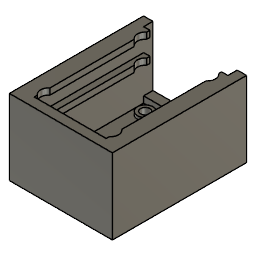
gy-neo6mv2_stand_v1 (Autodesk Fusion 360 design; units mm, degrees)
Autodesk Fusion 360 part; units mm, degrees
sketch "Sketch1" plane through (0, 0, 0) normal (0, 0, 1) x (1, 0, 0)
  line L0 (-13.5, 18.5) -> (13.5, 18.5)
  line L1 (13.5, 18.5) -> (13.5, -18.5)
  line L2 (13.5, -18.5) -> (-13.5, -18.5)
  line L3 (-13.5, -18.5) -> (-13.5, 18.5)
  line L4 (-16.5, 21.5) -> (16.5, 21.5)
  line L5 (16.5, 21.5) -> (16.5, -21.5)
  line L6 (16.5, -21.5) -> (-16.5, -21.5)
  line L7 (-16.5, -21.5) -> (-16.5, 21.5)
  circle A0 centre (-10, 15.5) radius 1.5
  circle A1 centre (10, 15.5) radius 1.5
  circle A2 centre (-10, -15.5) radius 1.5
  circle A3 centre (10, -15.5) radius 1.5
  circle A4 centre (-10, 15.5) radius 2.5
  circle A5 centre (10, 15.5) radius 2.5
  circle A6 centre (-10, -15.5) radius 2.5
  circle A7 centre (10, -15.5) radius 2.5
  line L8 (-13.5, 18.5) -> (-13.5, 21.5)
  line L9 (13.5, 18.5) -> (13.5, 21.5)
  line L10 (13.5, -18.5) -> (11.4824, -18.5)
  line L11 (11.4824, -18.5) -> (11.4824, 18.5)
  line L12 (11.4824, 18.5) -> (13.5, 18.5)
  line L13 (13.5, 18.5) -> (13.5, -18.5)
  line L14 (-13.5, -18.5) -> (-11.5071, -18.5)
  line L15 (-11.5071, -18.5) -> (-11.5071, 18.5)
  line L16 (-11.5071, 18.5) -> (-13.5, 18.5)
  line L17 (-13.5, 18.5) -> (-13.5, -18.5)
  dimension "d1" = 27
  dimension "d2" = 37
  dimension "d3" = 3
  dimension "d4" = 3
  dimension "d5" = 3
  dimension "d6" = 3
  dimension "d7" = 18.5
  dimension "d8" = 13.5
  dimension "d9" = 3
  dimension "d11" = 3
  dimension "d12" = 3.5
  dimension "d13" = 3
  dimension "d14" = 3
  dimension "d15" = 3
  dimension "d16" = 3
  dimension "d17" = 6.5
  dimension "d18" = 3
  dimension "d19" = 3
  dimension "d24" = 5
  dimension "d25" = 5
  dimension "d26" = 5
  dimension "d27" = 5
  constraint horizontal L0
  constraint vertical L1
  constraint horizontal L2
  constraint vertical L3
  constraint horizontal L4
  constraint vertical L5
  constraint horizontal L6
  constraint vertical L7
  constraint concentric A0 A4
  constraint concentric A1 A5
  constraint concentric A2 A6
  constraint concentric A3 A7
  constraint coincident L4 L8.end
  constraint perpendicular L4 L8
  constraint coincident L4 L9.end
  constraint perpendicular L4 L9
  constraint horizontal L10
  constraint vertical L11
  constraint horizontal L12
  constraint vertical L13
  constraint coincident L0 L11.end
  constraint horizontal L14
  constraint vertical L15
  constraint horizontal L16
  constraint vertical L17
  constraint coincident L0 L15.end
  measures "d1" distance of L0.start L0.end
  measures "d2" distance of L0.end L1.end
  measures "d3" distance of L0 L4
  measures "d4" distance of L1 L5
  measures "d5" distance of L3 L7
  measures "d6" distance of L2 L6
  measures "d7" vertical distance of origin L0.end
  measures "d8" horizontal distance of origin L0.end
  measures "d9" diameter of A0
  measures "d11" distance of L0 A0.centre
  measures "d12" distance of L3 A0.centre
  measures "d13" diameter of A1
  measures "d14" diameter of A2
  measures "d15" diameter of A3
  measures "d16" distance of L0 A1.centre
  measures "d17" distance of L5 A1.centre
  measures "d18" distance of L2 A3.centre
  measures "d19" distance of L2 A2.centre
  measures "d24" diameter of A4
  measures "d25" diameter of A5
  measures "d26" diameter of A6
  measures "d27" diameter of A7
extrude "Extrude1" add sketch "Sketch1" along normal blind 3 contours L0 L4 L8 L9 L12 L16 | L0 L2 L3 A4 A6 L14 L15 L16 L17 | L1 L2 L3 L4 L5 L6 L7 L8 L9 L10 L13 L14 L17 | L0 L2 A4 A5 A6 A7 L11 L15 | L0 L1 L2 A5 A7 L10 L11 L12 L13 | A4 L15 | A4 L15 | A1 A5 L11 | A1 A5 L11 | A6 L15 | A6 L15 | A3 A7 L11 | A3 A7 L11
extrude "Extrude2" add sketch "Sketch1" along normal blind 24.2 contours L1 L2 L3 L4 L5 L6 L7 L8 L9 L10 L13 L14 L17
extrude "Extrude3" add sketch "Sketch1" along normal blind 4 contours A4 L15 | A4 L15 | A1 A5 L11 | A1 A5 L11 | A6 L15 | A6 L15 | A3 A7 L11 | A3 A7 L11
extrude "Extrude4" add sketch "Sketch1" along normal blind 2 from surface at 15 contours L0 L2 L3 A4 A6 L14 L15 L16 L17 | L0 L1 L2 A5 A7 L10 L11 L12 L13
extrude "Extrude5" add 2 faces at (13.1473, -4.988, 17) (-13.1478, -4.9904, 17) along direction (0, 0, 1) blind 2 from surface at 5.2
extrude "Extrude6" add sketch "Sketch1" along normal blind 5 contours L0 L4 L8 L9 L12 L16
equation "d7 = ( 37 / 2 ) * 1 mm"
equation "d8 = ( 27 / 2 ) * 1 mm"
